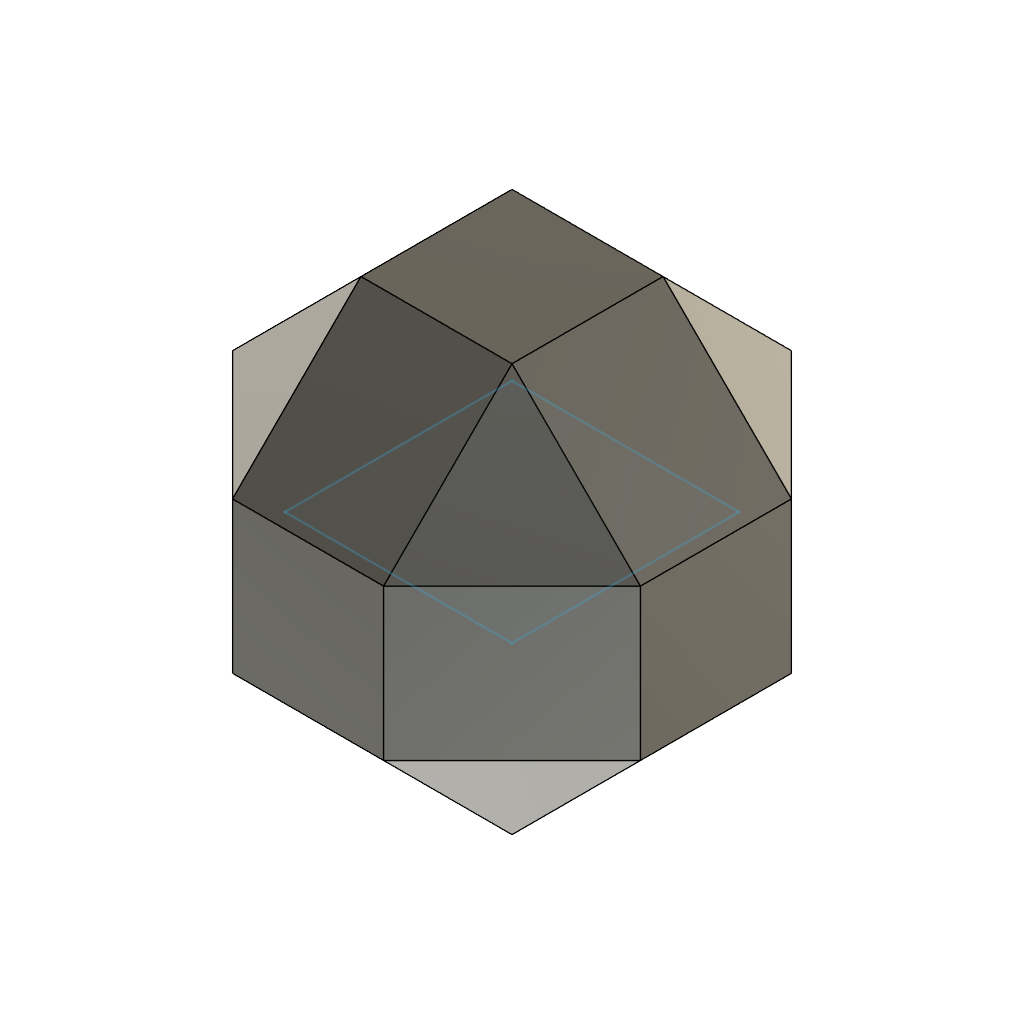
Core (Autodesk Fusion 360 design; units mm, degrees)
part number: 2026-10-12-20-18-52-341
Autodesk Fusion 360 part; units mm, degrees
sketch "Sketch1" plane through (0, 0, 0) normal (0, 0, 1) x (1, 0, 0)
  line L0 (-27, 27) -> (27, 27)
  line L1 (27, 27) -> (27, -27)
  line L2 (27, -27) -> (-27, -27)
  line L3 (-27, -27) -> (-27, 27)
  dimension "d1" = 54
  dimension "d2" = 54
  constraint horizontal L0
  constraint vertical L1
  constraint horizontal L2
  constraint vertical L3
  measures "d1" distance of L0.start L2.end
  measures "d2" distance of L1 L3
extrude "Extrude1" add sketch "Sketch1" along normal blind 27
extrude "Extrude2" add sketch "Sketch1" against normal blind 27
chamfer "Chamfer1" distance 17 angle 45 12 edges at (0, -27, -27) (27, 0, 27) (0, 27, 27) (27, -27, 0) (27, 0, -27) (0, -27, 27) (-27, 0, 27) (-27, -27, 0) (-27, 27, 0) (0, 27, -27) (-27, 0, -27) (27, 27, 0) tangent chain off
scale "Scale1" factor 1.794872 about (0, 0, 0) bodies 1
equation "d10 = 70 / 39"
